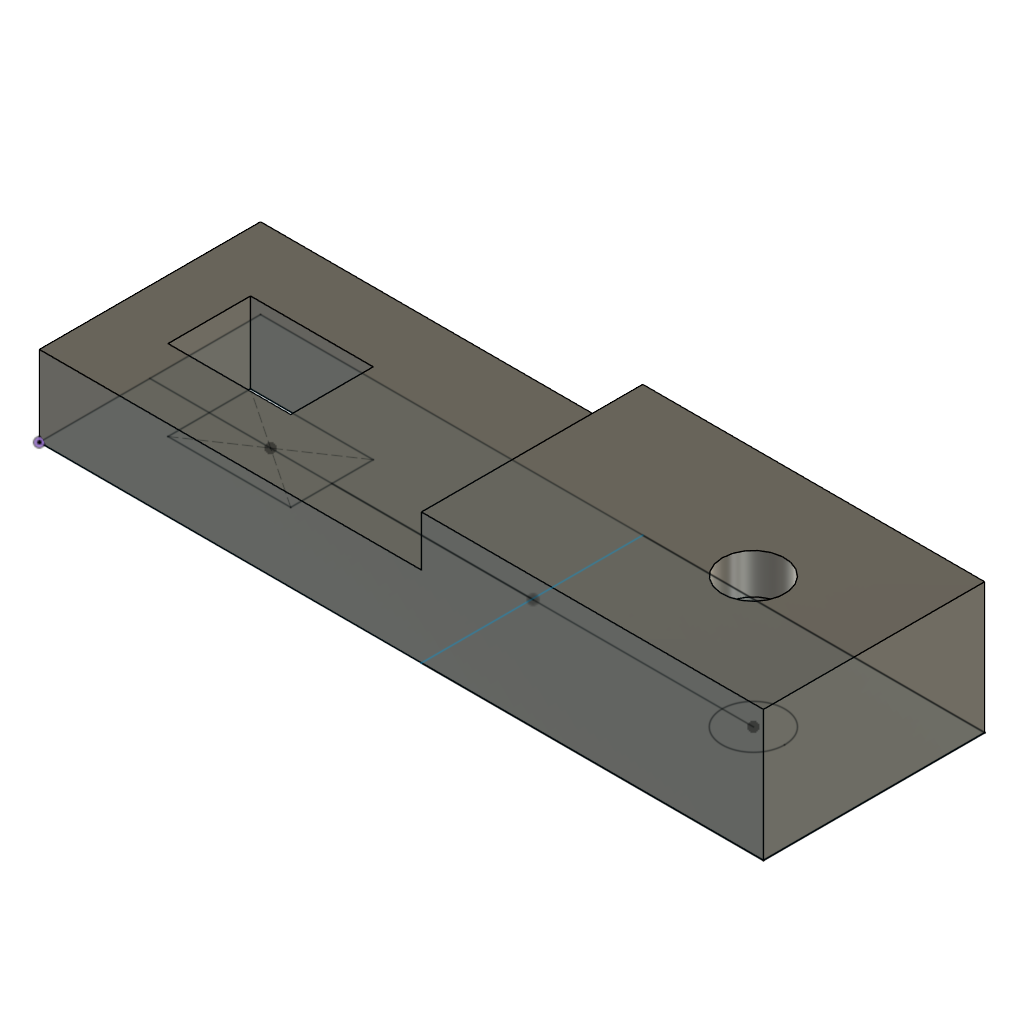
DL_servo_mount (Autodesk Fusion 360 archive; units mm, degrees)
design "valve handle"
part number: 2026-11-07-16-42-58-053
Autodesk Fusion 360 part; units mm, degrees
sketch "Sketch1" plane through (0, 0, 0) normal (0, 0, 1) x (1, 0, 0)
  line L0 (0, 0) -> (36, 0)
  line L1 (36, 0) -> (36, 11)
  line L2 (36, 11) -> (0, 11)
  line L3 (0, 11) -> (0, 0)
  line L4 (0, 5.5) -> (6, 5.5)
  line L5 (9.05, 3.45) -> (2.95, 3.45)
  line L6 (2.95, 3.45) -> (2.95, 7.55)
  line L7 (2.95, 7.55) -> (9.05, 7.55)
  line L8 (9.05, 7.55) -> (9.05, 3.45)
  line L9 (9.05, 3.45) -> (2.95, 7.55) construction
  line L10 (2.95, 3.45) -> (9.05, 7.55) construction
  line L11 (6, 5.5) -> (30, 5.5)
  circle A0 centre (30, 5.5) radius 1.55
  line L12 (9.05, 5.5) -> (19.05, 5.5)
  line L13 (19, 0) -> (36, 0)
  line L14 (36, 0) -> (36, 11)
  line L15 (36, 11) -> (19, 11)
  line L16 (19, 11) -> (19, 0)
  point P0 (6, 5.5)
  dimension "d1" = 36
  dimension "d2" = 11
  dimension "d3" = 6
  dimension "d4" = 5.5
  dimension "d9" = 6.1
  dimension "d10" = 4.1
  dimension "d11" = 24
  dimension "d12" = 3.1
  dimension "d18" = 10
  constraint horizontal L0
  constraint vertical L1
  constraint horizontal L2
  constraint vertical L3
  constraint coincident L0.start L3.end
  constraint coincident L3 L4.start
  constraint perpendicular L3 L4
  constraint horizontal L5
  constraint perpendicular L5 L6
  constraint parallel L5 L7
  constraint parallel L6 L8
  constraint coincident L9 P0
  constraint coincident L10 P0
  constraint coincident P0 L4.end
  constraint parallel L4 L11
  constraint coincident L11.end A0.centre
  constraint midpoint L8 L12.start
  constraint perpendicular L8 L12
  constraint horizontal L13
  constraint vertical L14
  constraint horizontal L15
  constraint vertical L16
  constraint coincident L0 L13.start
  measures "d1" distance of L1 L3
  measures "d2" distance of L0.end L1.end
  measures "d3" distance of L4.start P0
  measures "d4" distance of L2 L4
  measures "d9" distance of L5.start L5.end
  measures "d10" distance of L5.start L7.end
  measures "d11" distance of P0 L11.end
  measures "d12" diameter of A0
  measures "d18" distance of L12.start L12.end
extrude "Extrude2" add sketch "Sketch1" along normal blind 4 contours L0 L3 L4 L5 L6 L8 L11 L12 L16 | L0 L1 L2 L13 L14 L15 L16 | L2 L3 L4 L6 L7 L8 L11 L12 L16
extrude "Extrude3" add sketch "Sketch1" along normal blind 6.5 contours L0 L1 L2 L13 L14 L15 L16
sketch "Sketch3" plane through (0, 0, 0) normal (0, 0, 1) x (1, 0, 0)
  circle A0 centre (30, 5.5) radius 2.6
  dimension "d21" = 5.2
  measures "d21" diameter of A0
extrude "Extrude4" cut sketch "Sketch3" along normal blind 4.5
